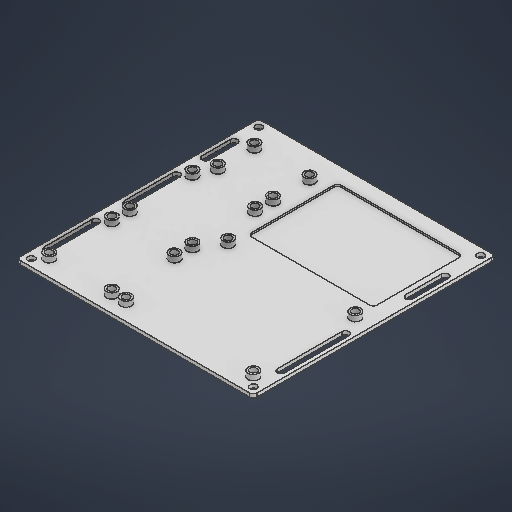
# Autodesk Inventor part: a
Saved by Autodesk Inventor 2026.2 (Build 302298010, 298A)
## iProperties
Created: 2026-03-20
Part Number: a
Material: 일반
Document SubType Name: Modeling
Designer: work
Density: 1 g/cm^3
Appearance: 기본값
Author: work
Autodesk Inventor part; units mm, degrees
ref_plane "YZ Plane" through (0, 0, 0) normal (1, 0, 0) x (0, 1, 0)
ref_plane "XZ Plane" through (0, 0, 0) normal (0, 1, 0) x (-1, 0, 0)
ref_plane "XY Plane" through (0, 0, 0) normal (0, 0, 1) x (1, 0, 0)
sketch "스케치1" plane through (0, 0, 0) normal (0, 1, 0) x (-1, 0, 0)
  line L0 (0, 0) -> (124, 0) construction
  line L1 (124, 0) -> (124, -127) construction
  line L2 (124, -127) -> (0, -127) construction
  line L3 (0, -127) -> (0, 0) construction
  circle A0 centre (5, -5) radius 3
  line L4 (5, -5) -> (76, -5) construction
  line L5 (76, -5) -> (76, -62) construction
  line L6 (76, -62) -> (5, -62) construction
  line L7 (5, -62) -> (5, -5) construction
  circle A1 centre (5, -62) radius 3
  circle A2 centre (76, -5) radius 3
  circle A3 centre (76, -62) radius 3
  line L8 (84, -5) -> (119, -5) construction
  line L9 (119, -5) -> (119, -40) construction
  line L10 (119, -40) -> (84, -40) construction
  line L11 (84, -40) -> (84, -5) construction
  circle A4 centre (119, -5) radius 3
  circle A5 centre (84, -5) radius 3
  circle A6 centre (84, -40) radius 3
  circle A7 centre (119, -40) radius 3
  line L12 (84, -50) -> (119, -50) construction
  line L13 (119, -50) -> (119, -85) construction
  line L14 (119, -85) -> (84, -85) construction
  line L15 (84, -85) -> (84, -50) construction
  circle A8 centre (119, -50) radius 3
  circle A9 centre (84, -50) radius 3
  circle A10 centre (84, -85) radius 3
  circle A11 centre (119, -85) radius 3
  line L16 (5, -72) -> (75, -72)
  line L17 (75, -72) -> (75, -122)
  line L18 (75, -122) -> (5, -122)
  line L19 (5, -122) -> (5, -72)
  line L20 (84, -95) -> (114.8, -95) construction
  line L21 (114.8, -95) -> (114.8, -115.4) construction
  line L22 (114.8, -115.4) -> (84, -115.4) construction
  line L23 (84, -115.4) -> (84, -95) construction
  circle A12 centre (84, -95) radius 3
  circle A13 centre (114.8, -95) radius 3
  circle A14 centre (114.8, -115.4) radius 3
  circle A15 centre (84, -115.4) radius 3
  line L24 (128, 4) -> (-4, 4)
  line L25 (-4, 4) -> (-4, -131)
  line L26 (-4, -131) -> (128, -131)
  line L27 (128, -131) -> (128, 4)
  circle A16 centre (0, 0) radius 2
  circle A17 centre (0, -127) radius 2
  circle A18 centre (124, -127) radius 2
  circle A19 centre (124, 0) radius 2
  point P0 (62, -127)
  dimension "d0" = 6
  dimension "d1" = 57
  dimension "d2" = 5
  dimension "d3" = 5
  dimension "d4" = 6
  dimension "d5" = 71
  dimension "d6" = 6
  dimension "d7" = 6
  dimension "d8" = 35
  dimension "d9" = 35
  dimension "d10" = 6
  dimension "d11" = 8
  dimension "d12" = 6
  dimension "d13" = 5
  dimension "d14" = 6
  dimension "d15" = 6
  dimension "d16" = 35
  dimension "d17" = 35
  dimension "d18" = 6
  dimension "d19" = 6
  dimension "d20" = 6
  dimension "d21" = 6
  dimension "d22" = 10
  dimension "d23" = 70
  dimension "d24" = 50
  dimension "d25" = 10
  dimension "d26" = 5
  dimension "d27" = 20.4
  dimension "d28" = 30.8
  dimension "d29" = 10
  dimension "d30" = 6
  dimension "d31" = 6
  dimension "d32" = 6
  dimension "d33" = 6
  dimension "d34" = 5
  dimension "d35" = 5
  dimension "d36" = 4
  dimension "d37" = 4
  dimension "d38" = 4
  dimension "d39" = 4
  dimension "d40" = 4
  dimension "d41" = 4
  dimension "d42" = 4
  dimension "d43" = 4
  constraints: 56 end point, 20 centre point, 19 coincident, 14 parallel, 7 horizontal, 7 perpendicular, 2 collinear, 1 midpoint
  measures "d0" diameter of A0
  measures "d1" distance of L6.end L4.start
  measures "d2" distance from line of L3 L4.start
  measures "d3" distance between parallel lines of L0 L4
  measures "d4" diameter of A1
  measures "d5" distance of L4.start L4.end
  measures "d6" diameter of A2
  measures "d7" diameter of A3
  measures "d8" distance of L9.end L10.end
  measures "d9" distance of L8.end L9.end
  measures "d10" diameter of A4
  measures "d11" distance of L4.end L8.start
  measures "d12" diameter of A5
  measures "d13" distance between parallel lines of L0 L8
  measures "d14" diameter of A6
  measures "d15" diameter of A7
  measures "d16" distance of L13.end L15.start
  measures "d17" distance of L13.start L13.end
  measures "d18" diameter of A8
  measures "d19" diameter of A9
  measures "d20" diameter of A10
  measures "d21" diameter of A11
  measures "d22" distance from line of L15.end L10
  measures "d23" distance of L17.end L18.end
  measures "d24" distance of L16.end L17.end
  measures "d25" distance between parallel lines of L6 L16
  measures "d26" distance between parallel lines of L3 L19
  measures "d27" distance of L20.end L21.end
  measures "d28" distance of L20.start L20.end
  measures "d29" distance of L15.start L20.start
  measures "d30" diameter of A12
  measures "d31" diameter of A13
  measures "d32" diameter of A14
  measures "d33" diameter of A15
  measures "d34" distance between parallel lines of L1 L13
  measures "d35" distance from line of point (62, -127) L18
  measures "d36" distance from line of L24 L0.start
  measures "d37" distance between parallel lines of L25 L3
  measures "d38" diameter of A16
  measures "d39" diameter of A17
  measures "d40" distance from line of L27 L1.end
  measures "d41" distance from line of L26 L1.end
  measures "d42" diameter of A18
  measures "d43" diameter of A19
extrude "돌출1" add sketch "스케치1" along normal blind 2 contours A0 | A1 | A2 | A3 | A4 | A5 | A6 | A7 | A8 | A9 | A10 | A11 | A12 | A13 | A14 | A15 | L27 L26 L25 L24
extrude "돌출2" add sketch "스케치1" along normal blind 5 contours A0 | A1 | A2 | A3 | A4 | A5 | A6 | A7 | A8 | A9 | A10 | A11 | A12 | A13 | A14 | A15
extrude "돌출3" add sketch "스케치1" along normal blind 1 contours L16 L17 L18 L19
sketch "스케치2" plane through (-5, 5, -5) normal (0, 1, 0) x (1, 0, 0)
  circle A0 centre (-71, 0) radius 3 projected
  circle A1 centre (-114, 45) radius 3 projected
  circle A2 centre (-79, 80) radius 3 projected
  circle A3 centre (-79, 110.4) radius 3 projected
  circle A4 centre (-79, 90) radius 3 projected
  circle A5 centre (-71, 57) radius 3 projected
  circle A6 centre (-114, 35) radius 3 projected
  circle A7 centre (0, 57) radius 3 projected
  circle A8 centre (-79, 0) radius 3 projected
  circle A9 centre (-79, 35) radius 3 projected
  circle A10 centre (-114, 80) radius 3 projected
  circle A11 centre (-109.8, 110.4) radius 3 projected
  circle A12 centre (-109.8, 90) radius 3 projected
  circle A13 centre (-79, 45) radius 3 projected
  circle A14 centre (-114, 0) radius 3 projected
  circle A15 centre (0, 0) radius 3 projected
  line L0 (9, -9) -> (9, 126) projected
  line L1 (9, 126) -> (-123, 126) projected
  line L2 (-123, 126) -> (-123, -9) projected
  line L3 (-123, -9) -> (9, -9) projected
  circle A16 centre (-119, 122) radius 2 projected
  circle A17 centre (5, 122) radius 2 projected
  circle A18 centre (-119, -5) radius 2 projected
  circle A19 centre (5, -5) radius 2 projected
  line L4 (0, 67) -> (-70, 67) projected
  line L5 (-70, 67) -> (-70, 117) projected
  line L6 (-70, 117) -> (0, 117) projected
  line L7 (0, 117) -> (0, 67) projected
  constraints: 16 coincident
hole "구멍1" at (-76, 5, -5) at (-84, 5, -5) at (-5, 5, -5) at (-5, 5, -62) at (-76, 5, -62) at (-84, 5, -50) at (-84, 5, -40) at (-119, 5, -5) at (-119, 5, -40) at (-119, 5, -50) at (-119, 5, -85) at (-84, 5, -85) at (-84, 5, -95) at (-114.8, 5, -95) at (-114.8, 5, -115.4) at (-84, 5, -115.4) direction (0, -1, 0) diameter 4 end through all
fillet "모깎기1" radius 2 8 edges at (-75, 1.5, -72) (-75, 1.5, -122) (-5, 1.5, -122) (-5, 1.5, -72) (4, 1, -131) (-128, 1, -131) (-128, 1, 4) (4, 1, 4)
sketch "스케치3" plane through (0, 2, 0) normal (0, 1, 0) x (1, 0, 0)
  arc A0 (2, -4) -> (4, -2) centre (2, -2) ccw projected
  line L0 (4, -2) -> (4, 129) projected
  arc A1 (4, 129) -> (2, 131) centre (2, 129) ccw projected
  line L1 (2, 131) -> (-126, 131) projected
  arc A2 (-126, 131) -> (-128, 129) centre (-126, 129) ccw projected
  line L2 (-128, 129) -> (-128, -2) projected
  arc A3 (-128, -2) -> (-126, -4) centre (-126, -2) ccw projected
  line L3 (-126, -4) -> (2, -4) projected
  circle A4 centre (-76, 5) radius 3 projected
  circle A5 centre (-119, 50) radius 3 projected
  circle A6 centre (-84, 85) radius 3 projected
  circle A7 centre (-84, 115.4) radius 3 projected
  circle A8 centre (-84, 95) radius 3 projected
  circle A9 centre (-76, 62) radius 3 projected
  circle A10 centre (-119, 40) radius 3 projected
  circle A11 centre (-5, 62) radius 3 projected
  circle A12 centre (-84, 5) radius 3 projected
  circle A13 centre (-84, 40) radius 3 projected
  circle A14 centre (-119, 85) radius 3 projected
  circle A15 centre (-114.8, 115.4) radius 3 projected
  circle A16 centre (-114.8, 95) radius 3 projected
  circle A17 centre (-84, 50) radius 3 projected
  circle A18 centre (-119, 5) radius 3 projected
  circle A19 centre (-5, 5) radius 3 projected
  circle A20 centre (-124, 127) radius 2 projected
  circle A21 centre (0, 127) radius 2 projected
  circle A22 centre (-124, 0) radius 2 projected
  circle A23 centre (0, 0) radius 2 projected
  line L4 (-7, 72) -> (-73, 72) projected
  arc A24 (-75, 74) -> (-73, 72) centre (-73, 74) ccw projected
  line L5 (-75, 74) -> (-75, 120) projected
  arc A25 (-73, 122) -> (-75, 120) centre (-73, 120) ccw projected
  line L6 (-73, 122) -> (-7, 122) projected
  arc A26 (-5, 120) -> (-7, 122) centre (-7, 120) ccw projected
  line L7 (-5, 120) -> (-5, 74) projected
  arc A27 (-7, 72) -> (-5, 74) centre (-7, 74) ccw projected
  circle A28 centre (-5, 5) radius 2 projected
  circle A29 centre (-5, 62) radius 2 projected
  line L8 (-5, 5) -> (-5, 62) construction
  line L9 (-124, 9) -> (-124, 36) construction
  line L10 (-122, 9) -> (-122, 36)
  line L11 (-126, 36) -> (-126, 9)
  arc A30 (-126, 9) -> (-122, 9) centre (-124, 9) ccw
  arc A31 (-122, 36) -> (-126, 36) centre (-124, 36) ccw
  line L12 (-119, 40) -> (-119, 50) construction
  line L13 (-119, 45) -> (-128, 45) construction
  line L14 (-124, 81) -> (-124, 54) construction
  line L15 (-122, 81) -> (-122, 54)
  line L16 (-126, 54) -> (-126, 81)
  arc A32 (-122, 81) -> (-126, 81) centre (-124, 81) ccw
  arc A33 (-126, 54) -> (-122, 54) centre (-124, 54) ccw
  line L17 (-114.8, 95) -> (-114.8, 115.4) construction
  line L18 (-114.8, 105.2) -> (-128, 105.2) construction
  line L19 (-124, 97.2) -> (-124, 113.2) construction
  line L20 (-122, 97.2) -> (-122, 113.2)
  line L21 (-126, 113.2) -> (-126, 97.2)
  arc A34 (-126, 97.2) -> (-122, 97.2) centre (-124, 97.2) ccw
  arc A35 (-122, 113.2) -> (-126, 113.2) centre (-124, 113.2) ccw
  line L22 (-5, 33.5) -> (4, 33.5) construction
  line L23 (0, 15.5) -> (0, 51.5) construction
  line L24 (2, 15.5) -> (2, 51.5)
  line L25 (-2, 51.5) -> (-2, 15.5)
  arc A36 (-2, 15.5) -> (2, 15.5) centre (0, 15.5) ccw
  arc A37 (2, 51.5) -> (-2, 51.5) centre (0, 51.5) ccw
  line L26 (-5, 97) -> (4, 97) construction
  line L27 (0, 87) -> (0, 107) construction
  line L28 (2, 87) -> (2, 107)
  line L29 (-2, 107) -> (-2, 87)
  arc A38 (-2, 87) -> (2, 87) centre (0, 87) ccw
  arc A39 (2, 107) -> (-2, 107) centre (0, 107) ccw
  point P0 (-124, 22.5)
  point P1 (-124, 67.5)
  point P2 (-124, 105.2)
  point P3 (0, 33.5)
  point P4 (0, 97)
  dimension "d58" = 4
  dimension "d59" = 4
  dimension "d60" = 4
  dimension "d61" = 4
  dimension "d62" = 8
  dimension "d63" = 4
  dimension "d64" = 4
  dimension "d65" = 18
  dimension "d66" = 4
  dimension "d67" = 4
  dimension "d68" = 10
  dimension "d69" = 4
  dimension "d70" = 4
  constraints: 54 end point, 20 point on circle, 16 tangent, 10 centre point, 8 midpoint, 7 perpendicular, 7 point on line, 7 symmetric about line, 4 parallel, 4 vertical, 2 other
  measures "d58" distance between parallel lines of L10 L11
  measures "d59" vertical distance of A18.centre L9.start
  measures "d60" vertical distance of L12.start L9.end
  measures "d61" distance from line of L2 point (-124, 22.5)
  measures "d62" distance of point (-124, 105.2) L19.end
  measures "d63" diameter of A35
  measures "d64" distance from line of L2 point (-124, 105.2)
  measures "d65" distance of point (0, 33.5) L23.end
  measures "d66" diameter of A37
  measures "d67" distance from line of L0 point (0, 33.5)
  measures "d68" distance of point (0, 97) L27.end
  measures "d69" diameter of A39
  measures "d70" distance from line of L0 point (0, 97)
extrude "돌출4" cut sketch "스케치3" against normal through all contours A30 L11 A31 L10 | L15 A33 L16 A32 | A34 L21 A35 L20 | A36 L25 A37 L24 | A38 L29 A39 L28
